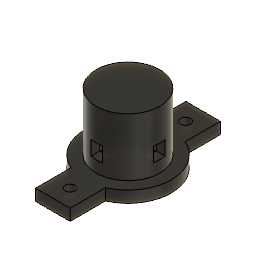
03_symmetric_brush_cartridge_15mm_V6_editable (Autodesk Fusion 360 design; units mm, degrees)
part number: 2026-10-22-00-18-10-099
Autodesk Fusion 360 part; units mm, degrees
ref_plane "作業平面1" through (0, 0, 8.5) normal (0, 0, 1) x (1, 0, 0)
sketch "スケッチ1" plane through (0, 0, 8.5) normal (0, 0, 1) x (1, 0, 0)
  circle A0 centre (78, 2.7629) radius 15
  dimension "d1327" = 30
  measures "d1327" diameter of A0
extrude "V5_symmetric_flange" add sketch "スケッチ1" along normal blind 4
ref_plane "作業平面2" through (0, 0, 8.5) normal (0, 0, 1) x (1, 0, 0)
sketch "スケッチ2" plane through (0, 0, 8.5) normal (0, 0, 1) x (1, 0, 0)
  line L0 (72, -23.2371) -> (84, -23.2371)
  line L1 (84, -23.2371) -> (84, -10.2371)
  line L2 (84, -10.2371) -> (72, -10.2371)
  line L3 (72, -10.2371) -> (72, -23.2371)
extrude "V5_symmetric_ear_-1 (1)" add sketch "スケッチ2" along normal blind 4
ref_plane "作業平面3" through (0, 0, 8.5) normal (0, 0, 1) x (1, 0, 0)
sketch "スケッチ3" plane through (0, 0, 8.5) normal (0, 0, 1) x (1, 0, 0)
  line L0 (72, 15.7629) -> (84, 15.7629)
  line L1 (84, 15.7629) -> (84, 28.7629)
  line L2 (84, 28.7629) -> (72, 28.7629)
  line L3 (72, 28.7629) -> (72, 15.7629)
extrude "V5_symmetric_ear_1 (1)" add sketch "スケッチ3" along normal blind 4
ref_plane "作業平面4" through (0, 0, 8.5) normal (0, 0, 1) x (1, 0, 0)
sketch "スケッチ4" plane through (0, 0, 8.5) normal (0, 0, 1) x (1, 0, 0)
  circle A0 centre (78, 2.7629) radius 11
  dimension "d1340" = 22
  measures "d1340" diameter of A0
extrude "V5_24mm_cartridge" add sketch "スケッチ4" along normal blind 24
ref_plane "作業平面5" through (0, 0, 8.5) normal (0, 0, 1) x (1, 0, 0)
sketch "スケッチ5" plane through (0, 0, 8.5) normal (0, 0, 1) x (1, 0, 0)
  circle A0 centre (78, 2.7629) radius 8
  dimension "d1345" = 16
  measures "d1345" diameter of A0
extrude "V5_brush_bore_with_butt_stop" cut sketch "スケッチ5" along normal blind 22
ref_plane "作業平面6" through (0, 0, 8.5) normal (0, 0, 1) x (1, 0, 0)
sketch "スケッチ6" plane through (0, 0, 8.5) normal (0, 0, 1) x (1, 0, 0)
  circle A0 centre (78, 2.7629) radius 11
  dimension "d1350" = 22
  measures "d1350" diameter of A0
extrude "V5_guide_land_8.5" add sketch "スケッチ6" along normal blind 2
ref_plane "作業平面7" through (0, 0, 8.5) normal (0, 0, 1) x (1, 0, 0)
sketch "スケッチ7" plane through (0, 0, 8.5) normal (0, 0, 1) x (1, 0, 0)
  circle A0 centre (78, 2.7629) radius 7.7
  dimension "d1355" = 15.4
  measures "d1355" diameter of A0
extrude "V5_brush_guide_8.5" cut sketch "スケッチ7" along normal blind 2
ref_plane "作業平面8" through (0, 0, 28.5) normal (0, 0, 1) x (1, 0, 0)
sketch "スケッチ8" plane through (0, 0, 28.5) normal (0, 0, 1) x (1, 0, 0)
  circle A0 centre (78, 2.7629) radius 11
  dimension "d1360" = 22
  measures "d1360" diameter of A0
extrude "V5_guide_land_28.5" add sketch "スケッチ8" along normal blind 2
ref_plane "作業平面9" through (0, 0, 28.5) normal (0, 0, 1) x (1, 0, 0)
sketch "スケッチ9" plane through (0, 0, 28.5) normal (0, 0, 1) x (1, 0, 0)
  circle A0 centre (78, 2.7629) radius 7.7
  dimension "d1365" = 15.4
  measures "d1365" diameter of A0
extrude "V5_brush_guide_28.5" cut sketch "スケッチ9" along normal blind 2
ref_plane "作業平面10" through (0, 0, 8.5) normal (0, 0, 1) x (1, 0, 0)
sketch "スケッチ10" plane through (0, 0, 8.5) normal (0, 0, 1) x (1, 0, 0)
  circle A0 centre (78, -17.2371) radius 1.7
  circle A1 centre (78, 22.7629) radius 1.7
  dimension "d1370" = 3.4
  dimension "d1371" = 3.4
  measures "d1370" diameter of A0
  measures "d1371" diameter of A1
extrude "V5_flange_M3_clearance" cut sketch "スケッチ10" along normal blind 4
ref_plane "作業平面11" through (65, 0, 0) normal (1, 0, 0) x (0, 1, 0)
sketch "スケッチ11" plane through (65, 0, 0) normal (1, 0, 0) x (0, 0, -1)
  line L0 (-16.5, 0.7629) -> (-16.5, 4.7629)
  line L1 (-16.5, 4.7629) -> (-21.5, 4.7629)
  line L2 (-21.5, 4.7629) -> (-21.5, 0.7629)
  line L3 (-21.5, 0.7629) -> (-16.5, 0.7629)
extrude "V5_X_glue_ports" cut sketch "スケッチ11" along normal blind 26
ref_plane "作業平面12" through (0, -10.2371, 0) normal (0, 1, 0) x (0, 0, 1)
sketch "スケッチ12" plane through (0, -10.2371, 0) normal (0, 1, 0) x (1, 0, 0)
  line L0 (76, -16.5) -> (80, -16.5)
  line L1 (80, -16.5) -> (80, -21.5)
  line L2 (80, -21.5) -> (76, -21.5)
  line L3 (76, -21.5) -> (76, -16.5)
extrude "V5_Y_glue_ports" cut sketch "スケッチ12" along normal blind 26
equation "d1327 = brush_flange_od"
equation "d1328 = brush_flange_thickness"
equation "d1340 = brush_cartridge_od"
equation "d1341 = v5_brush_sleeve_length"
equation "d1345 = brush_cartridge_id"
equation "d1346 = v5_brush_sleeve_length - 2 mm"
equation "d1350 = brush_cartridge_od"
equation "d1355 = brush_guide_dia"
equation "d1360 = brush_cartridge_od"
equation "d1365 = brush_guide_dia"
equation "d1370 = sc_screw_clearance"
equation "d1371 = sc_screw_clearance"
equation "brush_dia = 15 mm" comment "ç­è»¸ã®ç´å¾ â å®æ¸¬"
equation "sc_screw_clearance = 3.4 mm" comment "Printed base M3 clearance; sensor itself has M3 threaded holes"
equation "brush_glue_allowance = 1.0 mm" comment "Diametral allowance for hot glue around brush"
equation "brush_cartridge_od = 22 mm" comment "Rigid sleeve outside diameter; nominal wall 3 mm"
equation "brush_cartridge_id = brush_dia + brush_glue_allowance" comment "Nominal brush bore"
equation "brush_flange_od = brush_cartridge_od + 8 mm" comment "Cartridge load-bearing flange diameter"
equation "brush_flange_thickness = 4 mm" comment "Cartridge flange thickness"
equation "brush_guide_dia = brush_dia + 0.4 mm" comment "Slip guide at both sleeve ends; no clamp or interference fit"
equation "v5_brush_sleeve_length = 24 mm" comment "Shorter non-clamping hot glue cartridge; earlier versions retained"
named bodies: "V5_XY_mirror_symmetric_hot_glue_cartridge"
